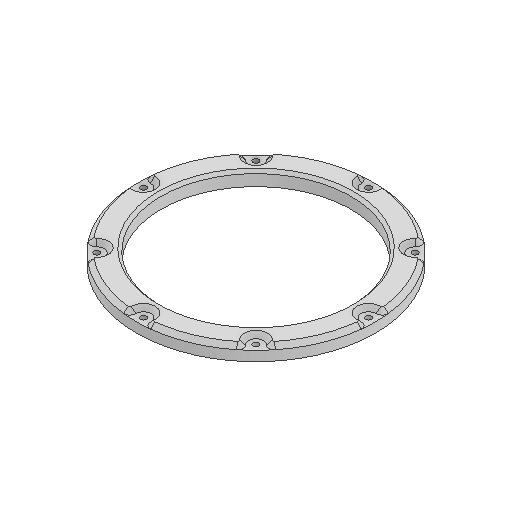
# Autodesk Inventor part: 3DP_PLA_A_Axis_Bearing_Base_Bearing_Locking_Ring
Saved by Autodesk Inventor 2027 (Build 310192060, 192F)
## iProperties
Created: 2026-01-06
Part Number: 3DP_PLA_A_Axis_Bearing_Base_Bearing_Locking_Ring
Material: Generic
Document SubType Name: Modeling
Designer: User
Density: 1 g/cm^3
Appearance: Default
Author: User
Autodesk Inventor part; units mm, degrees
ref_plane "YZ Plane" through (0, 0, 0) normal (1, 0, 0) x (0, 1, 0)
ref_plane "XZ Plane" through (0, 0, 0) normal (0, 1, 0) x (-1, 0, 0)
ref_plane "XY Plane" through (0, 0, 0) normal (0, 0, 1) x (1, 0, 0)
sketch "Sketch1" plane through (0, 0, 0) normal (0, 1, 0) x (-1, 0, 0)
  circle A0 centre (0, 0) radius 75
  circle A1 centre (0, 0) radius 85
  circle A2 centre (0, 0) radius 67.5
  circle A3 centre (0, 0) radius 100
  point P0 (0, -80)
  point P1 (56.5685, -56.5685)
  point P2 (80, 0)
  point P3 (56.5685, 56.5685)
  point P4 (0, 80)
  point P5 (-56.5685, 56.5685)
  point P6 (-80, 0)
  point P7 (-56.5685, -56.5685)
  dimension "d0" = 150
  dimension "d1" = 10
  dimension "d2" = 135
  dimension "d3" = 15
  dimension "d8" = 80
  dimension "d11" = 360
  constraints: 4 centre point, 2 coincident, 9 other
  measures "d0" diameter of A0
  measures "d1" radial gap between concentric circles of A0 A1
  measures "d2" diameter of A2
  measures "d3" radial gap between concentric circles of A1 A3
  measures "d8" distance of point (0, 0) point (0, -80)
extrude "Extrusion1" add sketch "Sketch1" against normal blind 10 contours A0 | A1
hole "Hole1" at (0, 0, -80) at (-56.5685, 0, -56.5685) at (-80, 0, 0) at (-56.5685, 0, 56.5685) at (0, 0, 80) at (56.5685, 0, 56.5685) at (80, 0, 0) at (56.5685, 0, -56.5685) direction (0, -1, 0) diameter 4.2 end through all
sketch "Sketch2" plane through (0, 0, 0) normal (0, 1, 0) x (1, 0, 0)
  circle A0 centre (56.5685, 56.5685) radius 2.1 projected
  circle A1 centre (80, 0) radius 2.1 projected
  circle A2 centre (56.5685, -56.5685) radius 2.1 projected
  circle A3 centre (0, -80) radius 2.1 projected
  circle A4 centre (-56.5685, -56.5685) radius 2.1 projected
  circle A5 centre (-80, 0) radius 2.1 projected
  circle A6 centre (-56.5685, 56.5685) radius 2.1 projected
  circle A7 centre (0, 80) radius 2.1 projected
  circle A8 centre (0, 0) radius 85 projected
  circle A9 centre (0, 0) radius 67.5 projected
hole "Hole2" at (-56.5685, 0, -56.5685) at (0, 0, -80) at (56.5685, 0, -56.5685) at (80, 0, 0) at (56.5685, 0, 56.5685) at (0, 0, 80) at (-56.5685, 0, 56.5685) at (-80, 0, 0) direction (0, -1, 0) diameter 10.5 depth 3
fillet "Fillet1" radius 4 2 edges at (-1.65, -1.5, 84.984) (1.65, -1.5, 84.984)
pattern_circular "Circular Pattern1" count 8 over 360 about axis through (0, 0, 0) along (0, -1, 0) of "Fillet1"
chamfer "Chamfer1" distance 3 angle 45 32 edges at (-32.5281, 0, 78.5298) (-6.5005, 0, 83.388) (0, 0, 74.75) (6.5005, 0, 83.388) (32.5281, 0, 78.5298) (54.3677, 0, 63.5608) (52.8562, 0, 52.8562) (63.5608, 0, 54.3677) (78.5298, 0, 32.5281) (83.388, 0, 6.5005) (74.75, 0, 0) (83.388, 0, -6.5005) (78.5298, 0, -32.5281) (63.5608, 0, -54.3677) (52.8562, 0, -52.8562) (54.3677, 0, -63.5608) (32.5281, 0, -78.5298) (6.5005, 0, -83.388) (0, 0, -74.75) (-6.5005, 0, -83.388) (-32.5281, 0, -78.5298) (-54.3677, 0, -63.5608) (-52.8562, 0, -52.8562) (-63.5608, 0, -54.3677) (-78.5298, 0, -32.5281) (-83.388, 0, -6.5005) (-74.75, 0, 0) (-83.388, 0, 6.5005) (-78.5298, 0, 32.5281) (-63.5608, 0, 54.3677) (-52.8562, 0, 52.8562) (-54.3677, 0, 63.5608)
chamfer "Chamfer2" distance 2 angle 45 1 edges at (67.5, 0, 0)
body "Solid1"
